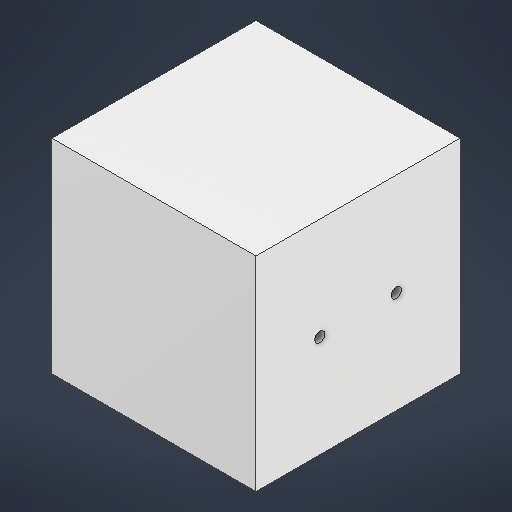
# Autodesk Inventor part: space
Saved by Autodesk Inventor 2026.1 (Build 301233000, 233)
## iProperties
Created: 2025-11-10
Part Number: space
Material: ABS Plastic
Document SubType Name: Modeling
Designer: shiva
Density: 1.06 g/cm^3
Appearance: Smooth - White
Author: shiva
Autodesk Inventor part; units mm, degrees
ref_plane "YZ Plane" through (0, 0, 0) normal (1, 0, 0) x (0, 1, 0)
ref_plane "XZ Plane" through (0, 0, 0) normal (0, 1, 0) x (-1, 0, 0)
ref_plane "XY Plane" through (0, 0, 0) normal (0, 0, 1) x (1, 0, 0)
sketch "Sketch1" plane through (0, 0, 0) normal (0, 0, 1) x (1, 0, 0)
  line L0 (-100, 100) -> (100, 100)
  line L1 (100, 100) -> (100, -100)
  line L2 (100, -100) -> (-100, -100)
  line L3 (-100, -100) -> (-100, 100)
  line L4 (-100, 100) -> (100, -100) construction
  line L5 (100, 100) -> (-100, -100) construction
  line L6 (81, -81) -> (-81, 81) construction
  line L7 (80, 80) -> (-80, -80) construction
  line L8 (-80, -80) -> (80, -80)
  line L9 (80, -80) -> (80, 80)
  line L10 (80, 80) -> (-80, 80)
  line L11 (-80, 80) -> (-80, -80)
  line L12 (-80, -80) -> (80, 80) construction
  line L13 (80, -80) -> (-80, 80) construction
  point P0 (0, 0)
  dimension "d2" = 200
  dimension "d6" = 160
  dimension "d7" = 160
  constraints: 28 end point, 6 midpoint, 4 parallel, 3 perpendicular, 2 horizontal, 1 point on line
  measures "d2" distance of L0.start L0.end
  measures "d6" distance of L10.end L7.start
  measures "d7" distance of L7.start L8.end
extrude "Extrusion1" add sketch "Sketch1" along normal blind 200
sketch "Sketch2" plane through (-80, -80, 0) normal (0, 1, 0) x (1, 0, 0)
  line L0 (0, 0) -> (180, 0)
  line L1 (180, 0) -> (180, -40)
  line L2 (180, -40) -> (0, -40)
  line L3 (0, -40) -> (0, 0)
  line L4 (160, -200) -> (0, -200) projected
  line L5 (0, -200) -> (180, -200)
  line L6 (180, -200) -> (180, -160)
  line L7 (180, -160) -> (0, -160)
  line L8 (0, -160) -> (0, -200)
  point P0 (80, 0)
  dimension "d8" = 180
  dimension "d9" = 40
  dimension "d10" = 180
  dimension "d11" = 40
  constraints: 16 end point, 4 parallel, 2 horizontal, 2 perpendicular
  measures "d8" distance of L1.end L2.end
  measures "d9" distance of L0.end L1.end
  measures "d10" distance of L7.end L6.end
  measures "d11" distance of L6.end L5.end
extrude "Extrusion2" add sketch "Sketch2" along normal up to next
sketch "Sketch5" plane through (-100, -100, 0) normal (-1, 0, 0) x (0, 0, 1)
  line L0 (0, 200) -> (200, 200) projected
  line L1 (200, 0) -> (200, 200) projected
  line L2 (0, 200) -> (200, 200)
  line L3 (200, 200) -> (200, 0)
  line L4 (200, 0) -> (0, 0)
  line L5 (0, 0) -> (0, 200)
  circle A0 centre (62.5, 100) radius 5
  circle A1 centre (137.5, 100) radius 5
  point P0 (0, 100)
  point P1 (200, 100)
  point P2 (0, 100)
  dimension "d19" = 10
  dimension "d27" = 10
  dimension "d28" = 75
  dimension "d29" = 62.5
  constraints: 8 end point, 2 centre point, 2 midpoint, 2 parallel, 1 horizontal, 1 perpendicular
  measures "d19" diameter of A0
  measures "d27" diameter of A1
  measures "d28" distance of A1.centre A0.centre
  measures "d29" distance of point (200, 100) A1.centre
extrude "Extrusion7" cut sketch "Sketch5" against normal through all contours A0 | A1
body "Solid1"
